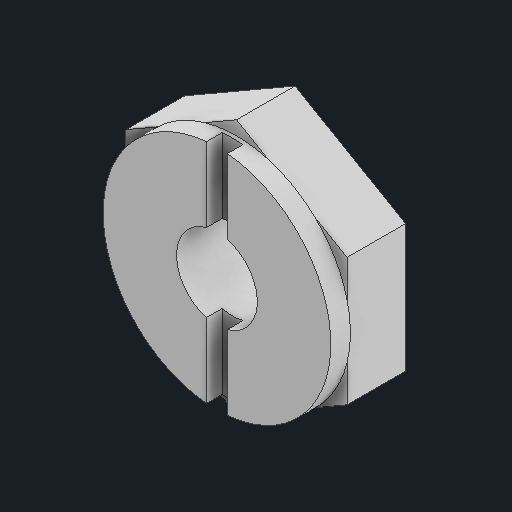
# Autodesk Inventor part: worm_nut_measured_6p0
Saved by Autodesk Inventor 2027.1 (Build 311270010, 270A)
## iProperties
Created: 2026-11-11
Part Number: worm_nut_measured_6p0
Material: Generic
Description: Worm bearing nut 17 AF + slotted collar 17.5, 6 mm from the block face (user measured 2026-11-11)
Document SubType Name: Modeling
Designer: alexg
Density: 1 g/cm^3
Appearance: Default
Author: alexg
Autodesk Inventor part; units mm, degrees
ref_plane "YZ Plane" through (0, 0, 0) normal (1, 0, 0) x (0, 1, 0)
sketch "Hex nut 17 AF sketch" plane through (0, 0, 0) normal (0, 0, 1) x (1, 0, 0)
  line L0 (8.5, 4.9075) -> (0, 9.815)
  line L1 (0, 9.815) -> (-8.5, 4.9075)
  line L2 (-8.5, 4.9075) -> (-8.5, -4.9075)
  line L3 (-8.5, -4.9075) -> (0, -9.815)
  line L4 (0, -9.815) -> (8.5, -4.9075)
  line L5 (8.5, -4.9075) -> (8.5, 4.9075)
  circle A0 centre (0, 0) radius 3.1
  constraints: 12 end point, 1 centre point
extrude "Hex nut 17 AF" add sketch "Hex nut 17 AF sketch" along normal blind 4.5
ref_plane "Work Plane1" through (0, 0, 4.5) normal (0, 0, 1) x (1, 0, 0)
sketch "Slotted collar 17.5 sketch" plane through (0, 0, 4.5) normal (0, 0, 1) x (1, 0, 0)
  circle A0 centre (0, 0) radius 8.75
  circle A1 centre (0, 0) radius 3.1
  constraints: 2 centre point
extrude "Slotted collar 17.5" add sketch "Slotted collar 17.5 sketch" along normal blind 1.5
ref_plane "Work Plane2" through (0, 0, 6) normal (0, 0, 1) x (1, 0, 0)
sketch "Collar slot sketch" plane through (0, 0, 6) normal (0, 0, 1) x (1, 0, 0)
  line L0 (-0.8, -9) -> (0.8, -9)
  line L1 (0.8, -9) -> (0.8, 9)
  line L2 (0.8, 9) -> (-0.8, 9)
  line L3 (-0.8, 9) -> (-0.8, -9)
  constraints: 8 end point, 2 parallel, 1 horizontal, 1 perpendicular
extrude "Collar slot" cut sketch "Collar slot sketch" against normal blind 1.2
body "Solid1"
